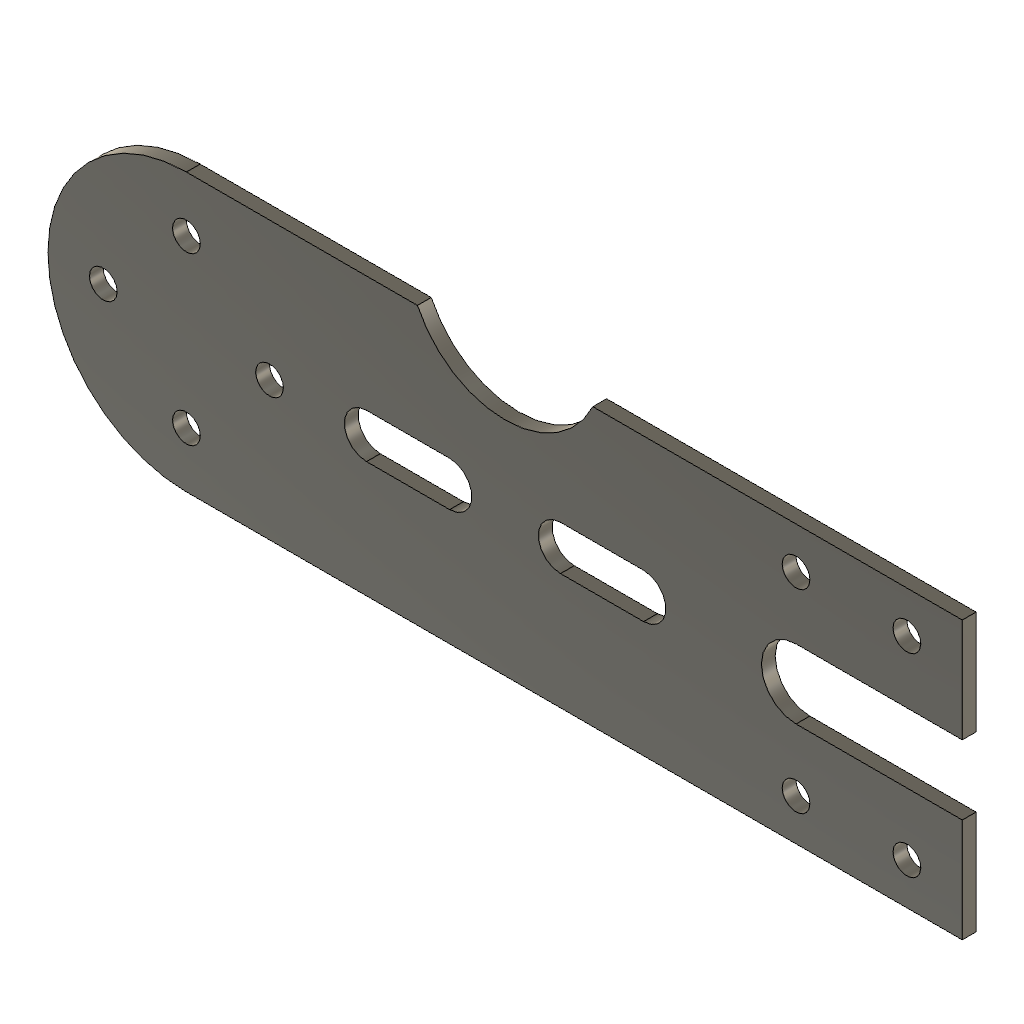
Exercise 2 v1 (Autodesk Fusion 360 design; units mm, degrees)
Autodesk Fusion 360 part; units mm, degrees
sketch "Sketch1" plane through (0, 0, 0) normal (0, 1, 0) x (1, 0, 0)
  line L0 (0, 0) -> (140, 0)
  line L1 (140, 0) -> (140, -100)
  line L2 (0, -100) -> (0, 0)
  arc A0 (101.6228, -100) -> (38.3772, -100) centre (70, -115) ccw
  line L3 (140, -100) -> (101.6228, -100)
  line L4 (38.3772, -100) -> (0, -100)
  line L5 (20, -58) -> (50, -58)
  arc A1 (50, -58) -> (50, -42) centre (50, -50) ccw
  line L6 (50, -42) -> (20, -42)
  arc A2 (20, -42) -> (20, -58) centre (20, -50) ccw
  line L7 (20, -50) -> (50, -50) construction
  line L8 (90, -58) -> (120, -58)
  arc A3 (120, -58) -> (120, -42) centre (120, -50) ccw
  line L9 (120, -42) -> (90, -42)
  arc A4 (90, -42) -> (90, -58) centre (90, -50) ccw
  line L10 (90, -50) -> (120, -50) construction
  line L11 (0, -100) -> (-45, -100)
  line L12 (0, 0) -> (-45, 0)
  arc A5 (-45, 0) -> (-45, -100) centre (-45, -50) ccw
  circle A6 centre (-45, -50) radius 30
  circle A7 centre (-45, -50) radius 15
  circle A8 centre (-45, -80) radius 5
  circle A9 centre (-15, -50) radius 5
  circle A10 centre (-45, -20) radius 5
  circle A11 centre (-75, -50) radius 5
  line L13 (140, 0) -> (140, -100)
  line L14 (140, -100) -> (235, -100)
  line L15 (235, -100) -> (235, -62.5)
  line L16 (235, -62.5) -> (175, -62.5)
  line L17 (175, -37.5) -> (235, -37.5)
  line L18 (235, -37.5) -> (235, 0)
  line L19 (235, 0) -> (140, 0)
  arc A12 (175, -37.5) -> (175, -62.5) centre (175, -50) ccw
  circle A13 centre (175, -85) radius 5
  circle A14 centre (215, -85) radius 5
  circle A15 centre (175, -15) radius 5
  circle A16 centre (215, -15) radius 5
  dimension "d1" = 140
  dimension "d2" = 100
  dimension "d3" = 15
  dimension "d4" = 70
  dimension "d5" = 70
  dimension "d6" = 8
  dimension "d7" = 8
  dimension "d8" = 20
  dimension "d9" = 30
  dimension "d10" = 40
  dimension "d11" = 30
  dimension "d12" = 50
  dimension "d13" = 45
  dimension "d14" = 45
  dimension "d15" = 100
  dimension "d16" = 45
  dimension "d17" = 60
  dimension "d18" = 30
  dimension "d19" = 10
  dimension "d21" = 360
  dimension "d23" = 95
  dimension "d24" = 60
  dimension "d25" = 25
  dimension "d26" = 60
  dimension "d27" = 25
  dimension "d28" = 10
  dimension "d29" = 35
  dimension "d30" = 10
  dimension "d31" = 40
  dimension "d32" = 15
  constraint horizontal L0
  constraint vertical L1
  constraint horizontal L3
  constraint vertical L2
  constraint coincident L0.start L2.end
  constraint coincident A0.end L3
  constraint collinear L3 L4
  constraint tangent L5 A1
  constraint tangent A1 L6
  constraint parallel L5 L6
  constraint tangent L6 A2
  constraint tangent L5 A2
  constraint perpendicular L2 L7
  constraint tangent L8 A3
  constraint tangent A3 L9
  constraint parallel L8 L9
  constraint tangent L9 A4
  constraint tangent L8 A4
  constraint parallel L6 L10
  constraint collinear L7 L10
  constraint perpendicular L2 L11
  constraint perpendicular L2 L12
  constraint concentric A5 A6
  constraint concentric A5 A7
  constraint coincident A6 A8.centre
  constraint vertical A5.centre A8.centre
  constraint vertical L13
  constraint perpendicular L13 L14
  constraint perpendicular L14 L15
  constraint perpendicular L1 L16
  constraint perpendicular L17 L18
  constraint perpendicular L1 L19
  constraint equal L15 L18
  constraint horizontal A13.centre A14.centre
  constraint symmetric L10 A13 A15
  constraint symmetric L10 A14 A16
  measures "d1" distance of L0.start L0.end
  measures "d2" distance of L0.start L2.start
  measures "d3" distance of A0.centre L3
  measures "d4" horizontal distance of L2.start A0.centre
  measures "d5" diameter of A0
  measures "d6" distance of L6.end A2.centre
  measures "d7" radius of A4
  measures "d8" distance of L2 A2.centre
  measures "d9" distance of A2.centre A1.centre
  measures "d10" horizontal distance of A1.centre A4.centre
  measures "d11" distance of A4.centre A3.centre
  measures "d12" distance of L0 L7
  measures "d13" distance of L2.start L11.end
  measures "d14" distance of L0.start L12.end
  measures "d15" diameter of A5
  measures "d16" distance of L2 A5.centre
  measures "d17" diameter of A6
  measures "d18" diameter of A7
  measures "d19" diameter of A8
  measures "d23" distance of L1.end L14.end
  measures "d24" distance of L15.end L16.end
  measures "d25" distance of L16.end L17.start
  measures "d26" distance of L17.start L17.end
  measures "d27" diameter of A12
  measures "d28" diameter of A13
  measures "d29" distance of L1 A13.centre
  measures "d30" diameter of A14
  measures "d31" horizontal distance of A13.centre A14.centre
  measures "d32" distance of L14 A13.centre
extrude "Extrude1" add sketch "Sketch1" along normal blind 5 contours L0 L1 L2 A0 L3 L4 L13 | L2 L11 L12 A5 | L1 L13 L14 L15 L16 L17 L18 L19 A12 | A6 A8 A9 A10 A11 | A7
